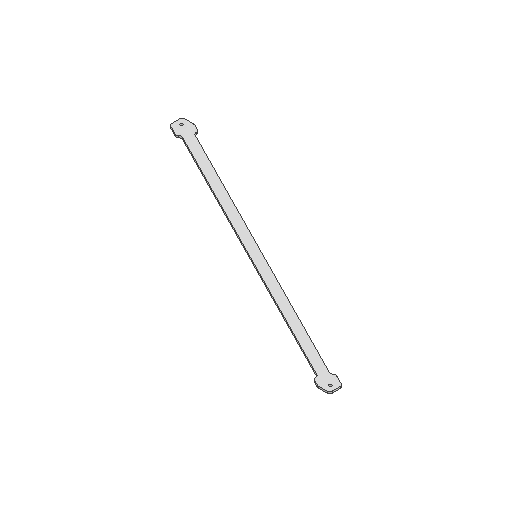
# Autodesk Inventor part: LC_3mm_ALU_Alu_Frame_Brace_REVB
Saved by Autodesk Inventor 2027 (Build 310192060, 192F)
## iProperties
Created: 2026-03-01
Part Number: LC_3mm_ALU_Alu_Frame_Brace_REVB
Material: Generic
Document SubType Name: Modeling
Designer: User
Density: 1 g/cm^3
Appearance: Default
Author: User
Autodesk Inventor part; units mm, degrees
ref_plane "YZ Plane" through (0, 0, 0) normal (1, 0, 0) x (0, 1, 0)
ref_plane "XZ Plane" through (0, 0, 0) normal (0, 1, 0) x (-1, 0, 0)
ref_plane "XY Plane" through (0, 0, 0) normal (0, 0, 1) x (1, 0, 0)
sketch "Sketch1" plane through (0, 0, 0) normal (0, 1, 0) x (-1, 0, 0)
  line L0 (0, 66.2319) -> (-20, 66.2319)
  line L1 (-20, 66.2319) -> (-20, 45.4519)
  line L2 (-20, 45.4519) -> (0, 45.4519)
  line L3 (0, 45.4519) -> (0, 66.2319)
  line L4 (500, -187.4781) -> (480, -187.4781)
  line L5 (480, -187.4781) -> (480, -208.2581)
  line L6 (480, -208.2581) -> (500, -208.2581)
  line L7 (500, -208.2581) -> (500, -187.4781)
  line L8 (500, -187.4781) -> (0, 66.2319)
  line L9 (-20, 45.4519) -> (480, -208.2581)
  point P0 (0, 0)
  point P1 (490, -197.2981)
  point P2 (-10, 55.2719)
  point P3 (500, -197.8681)
  dimension "d0" = 20.78
  dimension "d1" = 20
  dimension "d2" = 20
  dimension "d3" = 20.78
  dimension "d4" = 520
  dimension "d5" = 232.93
  dimension "d6" = 10
  dimension "d7" = 10.96
  dimension "d20" = 10.96
  dimension "d21" = 10
  constraints: 20 end point, 4 parallel, 2 horizontal, 2 perpendicular, 1 midpoint
  measures "d0" distance of L2.end L0.start
  measures "d1" distance of L0.start L0.end
  measures "d2" distance of L5.end L6.end
  measures "d3" distance of L4.end L5.end
  measures "d4" distance between parallel lines of L7 L1
  measures "d5" distance between parallel lines of L4 L2
  measures "d6" distance from line of point (-10, 55.272) L3
  measures "d7" distance from line of point (-10, 55.272) L0
  measures "d20" distance from line of L6 point (490, -197.298)
  measures "d21" distance from line of L7 point (490, -197.298)
extrude "Extrusion1" add sketch "Sketch1" along normal blind 3
hole "Hole1" at (-490, 0, -197.2981) at (10, 0, 55.2719) direction (0, 1, 0) diameter 4.5 end through all
fillet "Fillet1" radius 4 6 edges at (20, 1.5, 45.4519) (20, 1.5, 66.2319) (0, 1.5, 66.2319) (-480, 1.5, -208.2581) (-500, 1.5, -208.2581) (-500, 1.5, -187.4781)
sketch "Sketch2" plane through (0, 3, 0) normal (0, 1, 0) x (1, 0, 0)
  arc A0 (-500, 189.934) -> (-497.81, 186.3669) centre (-496, 189.934) ccw projected
  line L0 (-497.81, 186.3669) -> (-0.8532, -65.7989) projected
  arc A1 (-0.8532, -65.7989) -> (0.9568, -66.2319) centre (0.9568, -62.2319) ccw projected
  line L1 (0.9568, -66.2319) -> (16, -66.2319) projected
  arc A2 (16, -66.2319) -> (20, -62.2319) centre (16, -62.2319) ccw projected
  line L2 (20, -62.2319) -> (20, -47.9077) projected
  arc A3 (20, -47.9077) -> (17.81, -44.3406) centre (16, -47.9077) ccw projected
  line L3 (17.81, -44.3406) -> (-479.1468, 207.8252) projected
  arc A4 (-479.1468, 207.8252) -> (-480.9568, 208.2581) centre (-480.9568, 204.2581) ccw projected
  line L4 (-480.9568, 208.2581) -> (-496, 208.2581) projected
  arc A5 (-496, 208.2581) -> (-500, 204.2581) centre (-496, 204.2581) ccw projected
  line L5 (-500, 204.2581) -> (-500, 189.934) projected
  circle A6 centre (10, -55.2719) radius 2.25 projected
  circle A7 centre (-490, 197.2981) radius 2.25 projected
  line L6 (1.4352, -60.2319) -> (-494, 191.1619)
  line L7 (-494, 191.1619) -> (-494, 202.2581)
  line L8 (-494, 202.2581) -> (-481.4352, 202.2581)
  line L9 (-481.4352, 202.2581) -> (14, -49.1356)
  line L10 (14, -49.1356) -> (14, -60.2319)
  line L11 (14, -60.2319) -> (1.4352, -60.2319)
  line L12 (17.81, -44.3406) -> (-479.1468, 207.8252) projected
  line L13 (-478.1749, 176.4036) -> (-475.4599, 181.7542)
  line L14 (-468.4095, 195.6487) -> (-465.6945, 200.9993)
  line L15 (-14.3055, -58.973) -> (-11.5905, -53.6224)
  line L16 (-4.5401, -39.7279) -> (-1.5518, -33.8387)
  point P0 (0, 0)
  point P1 (-1.8251, -34.3773)
  dimension "d22" = 6
  dimension "d25" = 20
  dimension "d26" = 20
  dimension "d27" = 20
  dimension "d28" = 20
  constraints: 20 end point, 7 point on line, 6 perpendicular, 5 other
  measures "d22" distance between parallel lines of L0 L6
  measures "d25" distance from line of A6.centre L16
  measures "d26" distance from line of A6.centre L15
  measures "d27" distance from line of L14 A7.centre
  measures "d28" distance from line of L13 A7.centre
extrude "Extrusion2" cut sketch "Sketch2" against normal blind 10 contours L13 L6 L15 L0 | L3 L16 L9 L14
fillet "Fillet2" radius 5 8 edges at (-1.8251, 1.5, 34.3773) (-4.5401, 1.5, 39.7279) (-11.5905, 1.5, 53.6224) (-14.3055, 1.5, 58.973) (-475.4599, 1.5, -181.7542) (-478.1749, 1.5, -176.4036) (-468.4095, 1.5, -195.6487) (-465.6945, 1.5, -200.9993)
equation "\"d3\" = d0"
equation "\"d25\" = d27"
equation "\"d26\" = d27"
equation "\"d28\" = d27"
body "Solid1"
